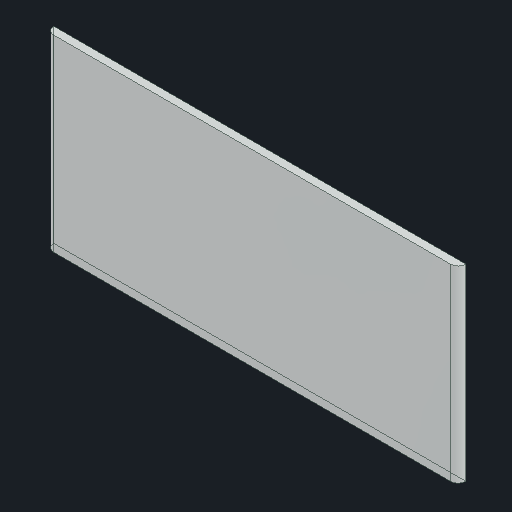
# Autodesk Inventor part: 7_6_1_part_brise
Saved by Autodesk Inventor 2026 (Build 300175000, 175)
## iProperties
Created: 2025-06-22
Part Number: 7_6_1_part_brise
Material: Glass
Document SubType Name: Modeling
Designer: remg9
Density: 2.18 g/cm^3
Appearance: Clear
Author: remg9
Autodesk Inventor part; units mm, degrees
ref_plane "YZ Plane" through (0, 0, 0) normal (1, 0, 0) x (0, 1, 0)
ref_plane "XZ Plane" through (0, 0, 0) normal (0, 1, 0) x (-1, 0, 0)
ref_plane "XY Plane" through (0, 0, 0) normal (0, 0, 1) x (1, 0, 0)
sketch "Sketch1" plane through (0, 0, 0) normal (0, 0, 1) x (1, 0, 0)
  line L0 (0, 0) -> (160.3, 0)
  line L1 (160.3, 0) -> (160.3, 73.13)
  line L2 (160.3, 73.13) -> (0, 73.13)
  line L3 (0, 73.13) -> (0, 0)
  point P0 (160.3, 36.565)
  dimension "d2" = 160.3
  dimension "d3" = 73.13
  constraints: 8 end point, 2 parallel, 1 horizontal, 1 midpoint, 1 perpendicular
  measures "d2" distance between parallel lines of L1 L3
  measures "d3" distance between parallel lines of L2 L0
extrude "Extrusion1" add sketch "Sketch1" along normal blind 3
fillet "Fillet1" radius 3 2 edges at (160.3, 36.565, 3) (0, 36.565, 3)
body "Solid1"
